Autodesk Fusion 360 part; units mm, degrees
(part 4 of 8)
sketch "SW5 spring 2 release 1 profile" plane through (0, -2.056, 23.4999) normal (0, -0.087156, 0.996195) x (1, 0, 0)
  line L0 (45.7157, 53.0972) -> (49.3, 53.0972)
  line L1 (49.3, 53.0972) -> (49.3, 53.6972)
  line L2 (49.3, 53.6972) -> (45.7157, 53.6972)
  line L3 (45.7157, 53.6972) -> (45.7157, 53.0972)
  dimension "d1355" = 45.7157
  dimension "d1356" = 53.0972
  dimension "d1357" = 3.5843
  dimension "d1358" = 0.6
  constraint horizontal L0
  constraint vertical L1
  constraint horizontal L2
  constraint vertical L3
  measures "d1355" horizontal distance of origin L0.start
  measures "d1356" vertical distance of origin L0.start
  measures "d1357" distance of L0.start L0.end
  measures "d1358" distance of L0.end L1.end
extrude "SW5 spring 2 release 1" cut sketch "SW5 spring 2 release 1 profile" against normal blind 10.7 bodies 2
sketch "SW5 spring 2 release 2 profile" plane through (0, -2.056, 23.4999) normal (0, -0.087156, 0.996195) x (1, 0, 0)
  line L0 (45.7157, 55.6972) -> (49.3, 55.6972)
  line L1 (49.3, 55.6972) -> (49.3, 56.2972)
  line L2 (49.3, 56.2972) -> (45.7157, 56.2972)
  line L3 (45.7157, 56.2972) -> (45.7157, 55.6972)
  dimension "d1361" = 45.7157
  dimension "d1362" = 55.6972
  dimension "d1363" = 3.5843
  dimension "d1364" = 0.6
  constraint horizontal L0
  constraint vertical L1
  constraint horizontal L2
  constraint vertical L3
  measures "d1361" horizontal distance of origin L0.start
  measures "d1362" vertical distance of origin L0.start
  measures "d1363" distance of L0.start L0.end
  measures "d1364" distance of L0.end L1.end
extrude "SW5 spring 2 release 2" cut sketch "SW5 spring 2 release 2 profile" against normal blind 10.7 bodies 2
sketch "SW5 spring 2 inner clearance profile" plane through (0, -1.6638, 19.017) normal (0, -0.087156, 0.996195) x (1, 0, 0)
  line L0 (45.7157, 53.6972) -> (48.4, 53.6972)
  line L1 (48.4, 53.6972) -> (48.4, 55.6972)
  line L2 (48.4, 55.6972) -> (45.7157, 55.6972)
  line L3 (45.7157, 55.6972) -> (45.7157, 53.6972)
  dimension "d1367" = 45.7157
  dimension "d1368" = 53.6972
  dimension "d1369" = 2.6843
  dimension "d1370" = 2
  constraint horizontal L0
  constraint vertical L1
  constraint horizontal L2
  constraint vertical L3
  measures "d1367" horizontal distance of origin L0.start
  measures "d1368" vertical distance of origin L0.start
  measures "d1369" distance of L0.start L0.end
  measures "d1370" distance of L0.end L1.end
extrude "SW5 spring 2 inner clearance" cut sketch "SW5 spring 2 inner clearance profile" against normal blind 6.2 bodies 2
sketch "SW5 spring 2 hook profile" plane through (0, -1.2106, 13.8368) normal (0, -0.087156, 0.996195) x (1, 0, 0)
  line L0 (45.2157, 53.6972) -> (49.2, 53.6972)
  line L1 (49.2, 53.6972) -> (49.2, 55.6972)
  line L2 (49.2, 55.6972) -> (45.2157, 55.6972)
  line L3 (45.2157, 55.6972) -> (45.2157, 53.6972)
  dimension "d1373" = 45.2157
  dimension "d1374" = 53.6972
  dimension "d1375" = 3.9843
  dimension "d1376" = 2
  constraint horizontal L0
  constraint vertical L1
  constraint horizontal L2
  constraint vertical L3
  measures "d1373" horizontal distance of origin L0.start
  measures "d1374" vertical distance of origin L0.start
  measures "d1375" distance of L0.start L0.end
  measures "d1376" distance of L0.end L1.end
extrude "SW5 spring 2 retaining hook" add sketch "SW5 spring 2 hook profile" against normal blind 0.8 bodies 2
chamfer "SW5 spring 2 45 degree lead-in" distance 0.35 angle 45 1 edges at (45.2157, 53.3482, 17.807) tangent chain off on bodies 2
sketch "SW5 support 1 reinforced stem profile" plane through (0, 0, 2) normal (0, 0, 1) x (1, 0, 0)
  line L0 (36.3, 45.9145) -> (38.7, 45.9145)
  line L1 (38.7, 45.9145) -> (38.7, 50.9145)
  line L2 (38.7, 50.9145) -> (36.3, 50.9145)
  line L3 (36.3, 50.9145) -> (36.3, 45.9145)
  dimension "d1380" = 36.3
  dimension "d1381" = 45.9145
  dimension "d1382" = 2.4
  dimension "d1383" = 5
  constraint horizontal L0
  constraint vertical L1
  constraint horizontal L2
  constraint vertical L3
  measures "d1380" horizontal distance of origin L0.start
  measures "d1381" vertical distance of origin L0.start
  measures "d1382" distance of L0.start L0.end
  measures "d1383" distance of L0.end L1.end
extrude "SW5 support 1 reinforced stem" add sketch "SW5 support 1 reinforced stem profile" along normal blind 13.9777 bodies 3
sketch "SW5 support 1 profile" plane through (0, 0, 2) normal (0, 0, 1) x (1, 0, 0)
  line L0 (37, 46.9145) -> (38, 46.9145)
  line L1 (38, 46.9145) -> (38, 49.9145)
  line L2 (38, 49.9145) -> (37, 49.9145)
  line L3 (37, 49.9145) -> (37, 46.9145)
  dimension "d1386" = 37
  dimension "d1387" = 46.9145
  dimension "d1388" = 1
  dimension "d1389" = 3
  constraint horizontal L0
  constraint vertical L1
  constraint horizontal L2
  constraint vertical L3
  measures "d1386" horizontal distance of origin L0.start
  measures "d1387" vertical distance of origin L0.start
  measures "d1388" distance of L0.start L0.end
  measures "d1389" distance of L0.end L1.end
extrude "SW5 support 1" add sketch "SW5 support 1 profile" along normal blind 16.4777 bodies 3
sketch "SW5 support 1 cap profile" plane through (0, -1.1931, 13.6376) normal (0, -0.087156, 0.996195) x (1, 0, 0)
  line L0 (36.9, 47.7972) -> (38.1, 47.7972)
  line L1 (38.1, 47.7972) -> (38.1, 51.7972)
  line L2 (38.1, 51.7972) -> (36.9, 51.7972)
  line L3 (36.9, 51.7972) -> (36.9, 47.7972)
  dimension "d1392" = 36.9
  dimension "d1393" = 47.7972
  dimension "d1394" = 1.2
  dimension "d1395" = 4
  constraint horizontal L0
  constraint vertical L1
  constraint horizontal L2
  constraint vertical L3
  measures "d1392" horizontal distance of origin L0.start
  measures "d1393" vertical distance of origin L0.start
  measures "d1394" distance of L0.start L0.end
  measures "d1395" distance of L0.end L1.end
extrude "SW5 support 1 inclined cap" cut sketch "SW5 support 1 cap profile" along normal blind 39.0612 bodies 3
sketch "SW5 support 2 reinforced stem profile" plane through (0, 0, 2) normal (0, 0, 1) x (1, 0, 0)
  line L0 (41.3, 45.9145) -> (43.7, 45.9145)
  line L1 (43.7, 45.9145) -> (43.7, 50.9145)
  line L2 (43.7, 50.9145) -> (41.3, 50.9145)
  line L3 (41.3, 50.9145) -> (41.3, 45.9145)
  dimension "d1398" = 41.3
  dimension "d1399" = 45.9145
  dimension "d1400" = 2.4
  dimension "d1401" = 5
  constraint horizontal L0
  constraint vertical L1
  constraint horizontal L2
  constraint vertical L3
  measures "d1398" horizontal distance of origin L0.start
  measures "d1399" vertical distance of origin L0.start
  measures "d1400" distance of L0.start L0.end
  measures "d1401" distance of L0.end L1.end
extrude "SW5 support 2 reinforced stem" add sketch "SW5 support 2 reinforced stem profile" along normal blind 13.9777 bodies 3
sketch "SW5 support 2 profile" plane through (0, 0, 2) normal (0, 0, 1) x (1, 0, 0)
  line L0 (42, 46.9145) -> (43, 46.9145)
  line L1 (43, 46.9145) -> (43, 49.9145)
  line L2 (43, 49.9145) -> (42, 49.9145)
  line L3 (42, 49.9145) -> (42, 46.9145)
  dimension "d1404" = 42
  dimension "d1405" = 46.9145
  dimension "d1406" = 1
  dimension "d1407" = 3
  constraint horizontal L0
  constraint vertical L1
  constraint horizontal L2
  constraint vertical L3
  measures "d1404" horizontal distance of origin L0.start
  measures "d1405" vertical distance of origin L0.start
  measures "d1406" distance of L0.start L0.end
  measures "d1407" distance of L0.end L1.end
extrude "SW5 support 2" add sketch "SW5 support 2 profile" along normal blind 16.4777 bodies 3
sketch "SW5 support 2 cap profile" plane through (0, -1.1931, 13.6376) normal (0, -0.087156, 0.996195) x (1, 0, 0)
  line L0 (41.9, 47.7972) -> (43.1, 47.7972)
  line L1 (43.1, 47.7972) -> (43.1, 51.7972)
  line L2 (43.1, 51.7972) -> (41.9, 51.7972)
  line L3 (41.9, 51.7972) -> (41.9, 47.7972)
  dimension "d1410" = 41.9
  dimension "d1411" = 47.7972
  dimension "d1412" = 1.2
  dimension "d1413" = 4
  constraint horizontal L0
  constraint vertical L1
  constraint horizontal L2
  constraint vertical L3
  measures "d1410" horizontal distance of origin L0.start
  measures "d1411" vertical distance of origin L0.start
  measures "d1412" distance of L0.start L0.end
  measures "d1413" distance of L0.end L1.end
extrude "SW5 support 2 inclined cap" cut sketch "SW5 support 2 cap profile" along normal blind 39.0612 bodies 3
sketch "SW6 receiver profile" plane through (0, -2.1431, 24.4961) normal (0, -0.087156, 0.996195) x (1, 0, 0)
  line L0 (55.3, 42.1972) -> (73.7, 42.1972)
  line L1 (73.7, 42.1972) -> (73.7, 59.7972)
  line L2 (73.7, 59.7972) -> (55.3, 59.7972)
  line L3 (55.3, 59.7972) -> (55.3, 42.1972)
  dimension "d1416" = 55.3
  dimension "d1417" = 42.1972
  dimension "d1418" = 18.4
  dimension "d1419" = 17.6
  constraint horizontal L0
  constraint vertical L1
  constraint horizontal L2
  constraint vertical L3
  measures "d1416" horizontal distance of origin L0.start
  measures "d1417" vertical distance of origin L0.start
  measures "d1418" distance of L0.start L0.end
  measures "d1419" distance of L0.end L1.end
extrude "SW6 integrated receiver" add sketch "SW6 receiver profile" against normal blind 11.5 bodies 2
sketch "SW6 switch lower clearance profile" plane through (0, -2.1431, 24.4961) normal (0, -0.087156, 0.996195) x (1, 0, 0)
  line L0 (56.5, 42.9972) -> (72.5, 42.9972)
  line L1 (72.5, 42.9972) -> (72.5, 58.9972)
  line L2 (72.5, 58.9972) -> (56.5, 58.9972)
  line L3 (56.5, 58.9972) -> (56.5, 42.9972)
  dimension "d1422" = 56.5
  dimension "d1423" = 42.9972
  dimension "d1424" = 16
  dimension "d1425" = 16
  constraint horizontal L0
  constraint vertical L1
  constraint horizontal L2
  constraint vertical L3
  measures "d1422" horizontal distance of origin L0.start
  measures "d1423" vertical distance of origin L0.start
  measures "d1424" distance of L0.start L0.end
  measures "d1425" distance of L0.end L1.end
extrude "SW6 switch lower clearance" cut sketch "SW6 switch lower clearance profile" against normal blind 5.5 bodies 2
sketch "SW6 holder pocket profile" plane through (0, -1.6638, 19.017) normal (0, -0.087156, 0.996195) x (1, 0, 0)
  line L0 (58.7843, 45.9226) -> (70.2157, 45.9226)
  line L1 (70.2157, 45.9226) -> (70.2157, 56.0717)
  line L2 (70.2157, 56.0717) -> (58.7843, 56.0717)
  line L3 (58.7843, 56.0717) -> (58.7843, 45.9226)
  dimension "d1428" = 58.7843
  dimension "d1429" = 45.9226
  dimension "d1430" = 11.4315
  dimension "d1431" = 10.1491
  constraint horizontal L0
  constraint vertical L1
  constraint horizontal L2
  constraint vertical L3
  measures "d1428" horizontal distance of origin L0.start
  measures "d1429" vertical distance of origin L0.start
  measures "d1430" distance of L0.start L0.end
  measures "d1431" distance of L0.end L1.end
extrude "SW6 open-bottom holder pocket" cut sketch "SW6 holder pocket profile" against normal blind 6.2 bodies 2
sketch "SW6 spring 1 release 1 profile" plane through (0, -2.056, 23.4999) normal (0, -0.087156, 0.996195) x (1, 0, 0)
  line L0 (55.2, 53.0972) -> (58.7843, 53.0972)
  line L1 (58.7843, 53.0972) -> (58.7843, 53.6972)
  line L2 (58.7843, 53.6972) -> (55.2, 53.6972)
  line L3 (55.2, 53.6972) -> (55.2, 53.0972)
  dimension "d1434" = 55.2
  dimension "d1435" = 53.0972
  dimension "d1436" = 3.5843
  dimension "d1437" = 0.6
  constraint horizontal L0
  constraint vertical L1
  constraint horizontal L2
  constraint vertical L3
  measures "d1434" horizontal distance of origin L0.start
  measures "d1435" vertical distance of origin L0.start
  measures "d1436" distance of L0.start L0.end
  measures "d1437" distance of L0.end L1.end
extrude "SW6 spring 1 release 1" cut sketch "SW6 spring 1 release 1 profile" against normal blind 10.7 bodies 2
sketch "SW6 spring 1 release 2 profile" plane through (0, -2.056, 23.4999) normal (0, -0.087156, 0.996195) x (1, 0, 0)
  line L0 (55.2, 55.6972) -> (58.7843, 55.6972)
  line L1 (58.7843, 55.6972) -> (58.7843, 56.2972)
  line L2 (58.7843, 56.2972) -> (55.2, 56.2972)
  line L3 (55.2, 56.2972) -> (55.2, 55.6972)
  dimension "d1440" = 55.2
  dimension "d1441" = 55.6972
  dimension "d1442" = 3.5843
  dimension "d1443" = 0.6
  constraint horizontal L0
  constraint vertical L1
  constraint horizontal L2
  constraint vertical L3
  measures "d1440" horizontal distance of origin L0.start
  measures "d1441" vertical distance of origin L0.start
  measures "d1442" distance of L0.start L0.end
  measures "d1443" distance of L0.end L1.end
extrude "SW6 spring 1 release 2" cut sketch "SW6 spring 1 release 2 profile" against normal blind 10.7 bodies 2
sketch "SW6 spring 1 inner clearance profile" plane through (0, -1.6638, 19.017) normal (0, -0.087156, 0.996195) x (1, 0, 0)
  line L0 (56.1, 53.6972) -> (58.7843, 53.6972)
  line L1 (58.7843, 53.6972) -> (58.7843, 55.6972)
  line L2 (58.7843, 55.6972) -> (56.1, 55.6972)
  line L3 (56.1, 55.6972) -> (56.1, 53.6972)
  dimension "d1446" = 56.1
  dimension "d1447" = 53.6972
  dimension "d1448" = 2.6843
  dimension "d1449" = 2
  constraint horizontal L0
  constraint vertical L1
  constraint horizontal L2
  constraint vertical L3
  measures "d1446" horizontal distance of origin L0.start
  measures "d1447" vertical distance of origin L0.start
  measures "d1448" distance of L0.start L0.end
  measures "d1449" distance of L0.end L1.end
extrude "SW6 spring 1 inner clearance" cut sketch "SW6 spring 1 inner clearance profile" against normal blind 6.2 bodies 2
sketch "SW6 spring 1 hook profile" plane through (0, -1.2106, 13.8368) normal (0, -0.087156, 0.996195) x (1, 0, 0)
  line L0 (55.3, 53.6972) -> (59.2843, 53.6972)
  line L1 (59.2843, 53.6972) -> (59.2843, 55.6972)
  line L2 (59.2843, 55.6972) -> (55.3, 55.6972)
  line L3 (55.3, 55.6972) -> (55.3, 53.6972)
  dimension "d1452" = 55.3
  dimension "d1453" = 53.6972
  dimension "d1454" = 3.9843
  dimension "d1455" = 2
  constraint horizontal L0
  constraint vertical L1
  constraint horizontal L2
  constraint vertical L3
  measures "d1452" horizontal distance of origin L0.start
  measures "d1453" vertical distance of origin L0.start
  measures "d1454" distance of L0.start L0.end
  measures "d1455" distance of L0.end L1.end
extrude "SW6 spring 1 retaining hook" add sketch "SW6 spring 1 hook profile" against normal blind 0.8 bodies 2
chamfer "SW6 spring 1 45 degree lead-in" distance 0.35 angle 45 1 edges at (59.2843, 53.3482, 17.807) tangent chain off on bodies 2
sketch "SW6 spring 2 release 1 profile" plane through (0, -2.056, 23.4999) normal (0, -0.087156, 0.996195) x (1, 0, 0)
  line L0 (70.2157, 53.0972) -> (73.8, 53.0972)
  line L1 (73.8, 53.0972) -> (73.8, 53.6972)
  line L2 (73.8, 53.6972) -> (70.2157, 53.6972)
  line L3 (70.2157, 53.6972) -> (70.2157, 53.0972)
  dimension "d1459" = 70.2157
  dimension "d1460" = 53.0972
  dimension "d1461" = 3.5843
  dimension "d1462" = 0.6
  constraint horizontal L0
  constraint vertical L1
  constraint horizontal L2
  constraint vertical L3
  measures "d1459" horizontal distance of origin L0.start
  measures "d1460" vertical distance of origin L0.start
  measures "d1461" distance of L0.start L0.end
  measures "d1462" distance of L0.end L1.end
extrude "SW6 spring 2 release 1" cut sketch "SW6 spring 2 release 1 profile" against normal blind 10.7 bodies 2
sketch "SW6 spring 2 release 2 profile" plane through (0, -2.056, 23.4999) normal (0, -0.087156, 0.996195) x (1, 0, 0)
  line L0 (70.2157, 55.6972) -> (73.8, 55.6972)
  line L1 (73.8, 55.6972) -> (73.8, 56.2972)
  line L2 (73.8, 56.2972) -> (70.2157, 56.2972)
  line L3 (70.2157, 56.2972) -> (70.2157, 55.6972)
  dimension "d1465" = 70.2157
  dimension "d1466" = 55.6972
  dimension "d1467" = 3.5843
  dimension "d1468" = 0.6
  constraint horizontal L0
  constraint vertical L1
  constraint horizontal L2
  constraint vertical L3
  measures "d1465" horizontal distance of origin L0.start
  measures "d1466" vertical distance of origin L0.start
  measures "d1467" distance of L0.start L0.end
  measures "d1468" distance of L0.end L1.end
extrude "SW6 spring 2 release 2" cut sketch "SW6 spring 2 release 2 profile" against normal blind 10.7 bodies 2
sketch "SW6 spring 2 inner clearance profile" plane through (0, -1.6638, 19.017) normal (0, -0.087156, 0.996195) x (1, 0, 0)
  line L0 (70.2157, 53.6972) -> (72.9, 53.6972)
  line L1 (72.9, 53.6972) -> (72.9, 55.6972)
  line L2 (72.9, 55.6972) -> (70.2157, 55.6972)
  line L3 (70.2157, 55.6972) -> (70.2157, 53.6972)
  dimension "d1471" = 70.2157
  dimension "d1472" = 53.6972
  dimension "d1473" = 2.6843
  dimension "d1474" = 2
  constraint horizontal L0
  constraint vertical L1
  constraint horizontal L2
  constraint vertical L3
  measures "d1471" horizontal distance of origin L0.start
  measures "d1472" vertical distance of origin L0.start
  measures "d1473" distance of L0.start L0.end
  measures "d1474" distance of L0.end L1.end
extrude "SW6 spring 2 inner clearance" cut sketch "SW6 spring 2 inner clearance profile" against normal blind 6.2 bodies 2
sketch "SW6 spring 2 hook profile" plane through (0, -1.2106, 13.8368) normal (0, -0.087156, 0.996195) x (1, 0, 0)
  line L0 (69.7157, 53.6972) -> (73.7, 53.6972)
  line L1 (73.7, 53.6972) -> (73.7, 55.6972)
  line L2 (73.7, 55.6972) -> (69.7157, 55.6972)
  line L3 (69.7157, 55.6972) -> (69.7157, 53.6972)
  dimension "d1477" = 69.7157
  dimension "d1478" = 53.6972
  dimension "d1479" = 3.9843
  dimension "d1480" = 2
  constraint horizontal L0
  constraint vertical L1
  constraint horizontal L2
  constraint vertical L3
  measures "d1477" horizontal distance of origin L0.start
  measures "d1478" vertical distance of origin L0.start
  measures "d1479" distance of L0.start L0.end
  measures "d1480" distance of L0.end L1.end
extrude "SW6 spring 2 retaining hook" add sketch "SW6 spring 2 hook profile" against normal blind 0.8 bodies 2
chamfer "SW6 spring 2 45 degree lead-in" distance 0.35 angle 45 1 edges at (69.7157, 53.3482, 17.807) tangent chain off on bodies 2
sketch "SW6 support 1 reinforced stem profile" plane through (0, 0, 2) normal (0, 0, 1) x (1, 0, 0)
  line L0 (60.8, 45.9145) -> (63.2, 45.9145)
  line L1 (63.2, 45.9145) -> (63.2, 50.9145)
  line L2 (63.2, 50.9145) -> (60.8, 50.9145)
  line L3 (60.8, 50.9145) -> (60.8, 45.9145)
  dimension "d1484" = 60.8
  dimension "d1485" = 45.9145
  dimension "d1486" = 2.4
  dimension "d1487" = 5
  constraint horizontal L0
  constraint vertical L1
  constraint horizontal L2
  constraint vertical L3
  measures "d1484" horizontal distance of origin L0.start
  measures "d1485" vertical distance of origin L0.start
  measures "d1486" distance of L0.start L0.end
  measures "d1487" distance of L0.end L1.end
extrude "SW6 support 1 reinforced stem" add sketch "SW6 support 1 reinforced stem profile" along normal blind 13.9777 bodies 3
sketch "SW6 support 1 profile" plane through (0, 0, 2) normal (0, 0, 1) x (1, 0, 0)
  line L0 (61.5, 46.9145) -> (62.5, 46.9145)
  line L1 (62.5, 46.9145) -> (62.5, 49.9145)
  line L2 (62.5, 49.9145) -> (61.5, 49.9145)
  line L3 (61.5, 49.9145) -> (61.5, 46.9145)
  dimension "d1490" = 61.5
  dimension "d1491" = 46.9145
  dimension "d1492" = 1
  dimension "d1493" = 3
  constraint horizontal L0
  constraint vertical L1
  constraint horizontal L2
  constraint vertical L3
  measures "d1490" horizontal distance of origin L0.start
  measures "d1491" vertical distance of origin L0.start
  measures "d1492" distance of L0.start L0.end
  measures "d1493" distance of L0.end L1.end
extrude "SW6 support 1" add sketch "SW6 support 1 profile" along normal blind 16.4777 bodies 3
sketch "SW6 support 1 cap profile" plane through (0, -1.1931, 13.6376) normal (0, -0.087156, 0.996195) x (1, 0, 0)
  line L0 (61.4, 47.7972) -> (62.6, 47.7972)
  line L1 (62.6, 47.7972) -> (62.6, 51.7972)
  line L2 (62.6, 51.7972) -> (61.4, 51.7972)
  line L3 (61.4, 51.7972) -> (61.4, 47.7972)
  dimension "d1496" = 61.4
  dimension "d1497" = 47.7972
  dimension "d1498" = 1.2
  dimension "d1499" = 4
  constraint horizontal L0
  constraint vertical L1
  constraint horizontal L2
  constraint vertical L3
  measures "d1496" horizontal distance of origin L0.start
  measures "d1497" vertical distance of origin L0.start
  measures "d1498" distance of L0.start L0.end
  measures "d1499" distance of L0.end L1.end
extrude "SW6 support 1 inclined cap" cut sketch "SW6 support 1 cap profile" along normal blind 39.0612 bodies 3
sketch "SW6 support 2 reinforced stem profile" plane through (0, 0, 2) normal (0, 0, 1) x (1, 0, 0)
  line L0 (65.8, 45.9145) -> (68.2, 45.9145)
  line L1 (68.2, 45.9145) -> (68.2, 50.9145)
  line L2 (68.2, 50.9145) -> (65.8, 50.9145)
  line L3 (65.8, 50.9145) -> (65.8, 45.9145)
  dimension "d1502" = 65.8
  dimension "d1503" = 45.9145
  dimension "d1504" = 2.4
  dimension "d1505" = 5
  constraint horizontal L0
  constraint vertical L1
  constraint horizontal L2
  constraint vertical L3
  measures "d1502" horizontal distance of origin L0.start
  measures "d1503" vertical distance of origin L0.start
  measures "d1504" distance of L0.start L0.end
  measures "d1505" distance of L0.end L1.end
extrude "SW6 support 2 reinforced stem" add sketch "SW6 support 2 reinforced stem profile" along normal blind 13.9777 bodies 3
sketch "SW6 support 2 profile" plane through (0, 0, 2) normal (0, 0, 1) x (1, 0, 0)
  line L0 (66.5, 46.9145) -> (67.5, 46.9145)
  line L1 (67.5, 46.9145) -> (67.5, 49.9145)
  line L2 (67.5, 49.9145) -> (66.5, 49.9145)
  line L3 (66.5, 49.9145) -> (66.5, 46.9145)
  dimension "d1508" = 66.5
  dimension "d1509" = 46.9145
  dimension "d1510" = 1
  dimension "d1511" = 3
  constraint horizontal L0
  constraint vertical L1
  constraint horizontal L2
  constraint vertical L3
  measures "d1508" horizontal distance of origin L0.start
  measures "d1509" vertical distance of origin L0.start
  measures "d1510" distance of L0.start L0.end
  measures "d1511" distance of L0.end L1.end
extrude "SW6 support 2" add sketch "SW6 support 2 profile" along normal blind 16.4777 bodies 3
sketch "SW6 support 2 cap profile" plane through (0, -1.1931, 13.6376) normal (0, -0.087156, 0.996195) x (1, 0, 0)
  line L0 (66.4, 47.7972) -> (67.6, 47.7972)
  line L1 (67.6, 47.7972) -> (67.6, 51.7972)
  line L2 (67.6, 51.7972) -> (66.4, 51.7972)
  line L3 (66.4, 51.7972) -> (66.4, 47.7972)
  dimension "d1514" = 66.4
  dimension "d1515" = 47.7972
  dimension "d1516" = 1.2
  dimension "d1517" = 4
  constraint horizontal L0
  constraint vertical L1
  constraint horizontal L2
  constraint vertical L3
  measures "d1514" horizontal distance of origin L0.start
  measures "d1515" vertical distance of origin L0.start
  measures "d1516" distance of L0.start L0.end
  measures "d1517" distance of L0.end L1.end
extrude "SW6 support 2 inclined cap" cut sketch "SW6 support 2 cap profile" along normal blind 39.0612 bodies 3
sketch "OLED clearance after switch receivers profile" plane through (0, -2.2739, 25.9904) normal (0, -0.087156, 0.996195) x (1, 0, 0)
  line L0 (5.55, 59.2972) -> (41.95, 59.2972)
  line L1 (41.95, 59.2972) -> (41.95, 93.6972)
  line L2 (41.95, 93.6972) -> (5.55, 93.6972)
  line L3 (5.55, 93.6972) -> (5.55, 59.2972)
  dimension "d1520" = 5.55
  dimension "d1521" = 59.2972
  dimension "d1522" = 36.4
  dimension "d1523" = 34.4
  constraint horizontal L0
  constraint vertical L1
  constraint horizontal L2
  constraint vertical L3
  measures "d1520" horizontal distance of origin L0.start
  measures "d1521" vertical distance of origin L0.start
  measures "d1522" distance of L0.start L0.end
  measures "d1523" distance of L0.end L1.end
extrude "OLED clearance after switch receivers" cut sketch "OLED clearance after switch receivers profile" against normal blind 1.8 bodies 2
sketch "Switch trial plate profile" plane through (0, -2.2739, 25.9904) normal (0, -0.087156, 0.996195) x (1, 0, 0)
  line L0 (104, 15.4972) -> (126, 15.4972)
  line L1 (126, 15.4972) -> (126, 37.4972)
  line L2 (126, 37.4972) -> (104, 37.4972)
  line L3 (104, 37.4972) -> (104, 15.4972)
  dimension "d1526" = 104
  dimension "d1527" = 15.4972
  dimension "d1528" = 22
  dimension "d1529" = 22
  constraint horizontal L0
  constraint vertical L1
  constraint horizontal L2
  constraint vertical L3
  measures "d1526" horizontal distance of origin L0.start
  measures "d1527" vertical distance of origin L0.start
  measures "d1528" distance of L0.start L0.end
  measures "d1529" distance of L0.end L1.end
extrude "Switch trial plate" add sketch "Switch trial plate profile" against normal blind 1.5 separate body makes body 5
sketch "Switch trial clip seat profile" plane through (0, -2.2739, 25.9904) normal (0, -0.087156, 0.996195) x (1, 0, 0)
  line L0 (107.95, 19.4472) -> (122.05, 19.4472)
  line L1 (122.05, 19.4472) -> (122.05, 33.5472)
  line L2 (122.05, 33.5472) -> (107.95, 33.5472)
  line L3 (107.95, 33.5472) -> (107.95, 19.4472)
  dimension "d1532" = 107.95
  dimension "d1533" = 19.4472
  dimension "d1534" = 14.1
  dimension "d1535" = 14.1
  constraint horizontal L0
  constraint vertical L1
  constraint horizontal L2
  constraint vertical L3
  measures "d1532" horizontal distance of origin L0.start
  measures "d1533" vertical distance of origin L0.start
  measures "d1534" distance of L0.start L0.end
  measures "d1535" distance of L0.end L1.end
extrude "Switch trial clip seat" cut sketch "Switch trial clip seat profile" against normal blind 1.6 bodies 5
sketch "Switch trial receiver profile" plane through (0, -2.1431, 24.4961) normal (0, -0.087156, 0.996195) x (1, 0, 0)
  line L0 (105.8, 17.6972) -> (124.2, 17.6972)
  line L1 (124.2, 17.6972) -> (124.2, 35.2972)
  line L2 (124.2, 35.2972) -> (105.8, 35.2972)
  line L3 (105.8, 35.2972) -> (105.8, 17.6972)
  dimension "d1538" = 105.8
  dimension "d1539" = 17.6972
  dimension "d1540" = 18.4
  dimension "d1541" = 17.6
  constraint horizontal L0
  constraint vertical L1
  constraint horizontal L2
  constraint vertical L3
  measures "d1538" horizontal distance of origin L0.start
  measures "d1539" vertical distance of origin L0.start
  measures "d1540" distance of L0.start L0.end
  measures "d1541" distance of L0.end L1.end
extrude "Switch trial integrated receiver" add sketch "Switch trial receiver profile" against normal blind 11.5 bodies 5
sketch "Switch trial switch lower clearance profile" plane through (0, -2.1431, 24.4961) normal (0, -0.087156, 0.996195) x (1, 0, 0)
  line L0 (107, 18.4972) -> (123, 18.4972)
  line L1 (123, 18.4972) -> (123, 34.4972)
  line L2 (123, 34.4972) -> (107, 34.4972)
  line L3 (107, 34.4972) -> (107, 18.4972)
  dimension "d1544" = 107
  dimension "d1545" = 18.4972
  dimension "d1546" = 16
  dimension "d1547" = 16
  constraint horizontal L0
  constraint vertical L1
  constraint horizontal L2
  constraint vertical L3
  measures "d1544" horizontal distance of origin L0.start
  measures "d1545" vertical distance of origin L0.start
  measures "d1546" distance of L0.start L0.end
  measures "d1547" distance of L0.end L1.end
extrude "Switch trial switch lower clearance" cut sketch "Switch trial switch lower clearance profile" against normal blind 5.5 bodies 5
sketch "Switch trial holder pocket profile" plane through (0, -1.6638, 19.017) normal (0, -0.087156, 0.996195) x (1, 0, 0)
  line L0 (109.2843, 21.4226) -> (120.7157, 21.4226)
  line L1 (120.7157, 21.4226) -> (120.7157, 31.5717)
  line L2 (120.7157, 31.5717) -> (109.2843, 31.5717)
  line L3 (109.2843, 31.5717) -> (109.2843, 21.4226)
  dimension "d1550" = 109.2843
  dimension "d1551" = 21.4226
  dimension "d1552" = 11.4315
  dimension "d1553" = 10.1491
  constraint horizontal L0
  constraint vertical L1
  constraint horizontal L2
  constraint vertical L3
  measures "d1550" horizontal distance of origin L0.start
  measures "d1551" vertical distance of origin L0.start
  measures "d1552" distance of L0.start L0.end
  measures "d1553" distance of L0.end L1.end
extrude "Switch trial open-bottom holder pocket" cut sketch "Switch trial holder pocket profile" against normal blind 6.2 bodies 5
sketch "Switch trial spring 1 release 1 profile" plane through (0, -2.056, 23.4999) normal (0, -0.087156, 0.996195) x (1, 0, 0)
  line L0 (105.7, 28.5972) -> (109.2843, 28.5972)
  line L1 (109.2843, 28.5972) -> (109.2843, 29.1972)
  line L2 (109.2843, 29.1972) -> (105.7, 29.1972)
  line L3 (105.7, 29.1972) -> (105.7, 28.5972)
  dimension "d1556" = 105.7
  dimension "d1557" = 28.5972
  dimension "d1558" = 3.5843
  dimension "d1559" = 0.6
  constraint horizontal L0
  constraint vertical L1
  constraint horizontal L2
  constraint vertical L3
  measures "d1556" horizontal distance of origin L0.start
  measures "d1557" vertical distance of origin L0.start
  measures "d1558" distance of L0.start L0.end
  measures "d1559" distance of L0.end L1.end
extrude "Switch trial spring 1 release 1" cut sketch "Switch trial spring 1 release 1 profile" against normal blind 10.7 bodies 5
sketch "Switch trial spring 1 release 2 profile" plane through (0, -2.056, 23.4999) normal (0, -0.087156, 0.996195) x (1, 0, 0)
  line L0 (105.7, 31.1972) -> (109.2843, 31.1972)
  line L1 (109.2843, 31.1972) -> (109.2843, 31.7972)
  line L2 (109.2843, 31.7972) -> (105.7, 31.7972)
  line L3 (105.7, 31.7972) -> (105.7, 31.1972)
  dimension "d1562" = 105.7
  dimension "d1563" = 31.1972
  dimension "d1564" = 3.5843
  dimension "d1565" = 0.6
  constraint horizontal L0
  constraint vertical L1
  constraint horizontal L2
  constraint vertical L3
  measures "d1562" horizontal distance of origin L0.start
  measures "d1563" vertical distance of origin L0.start
  measures "d1564" distance of L0.start L0.end
  measures "d1565" distance of L0.end L1.end
extrude "Switch trial spring 1 release 2" cut sketch "Switch trial spring 1 release 2 profile" against normal blind 10.7 bodies 5
sketch "Switch trial spring 1 inner clearance profile" plane through (0, -1.6638, 19.017) normal (0, -0.087156, 0.996195) x (1, 0, 0)
  line L0 (106.6, 29.1972) -> (109.2843, 29.1972)
  line L1 (109.2843, 29.1972) -> (109.2843, 31.1972)
  line L2 (109.2843, 31.1972) -> (106.6, 31.1972)
  line L3 (106.6, 31.1972) -> (106.6, 29.1972)
  dimension "d1568" = 106.6
  dimension "d1569" = 29.1972
  dimension "d1570" = 2.6843
  dimension "d1571" = 2
  constraint horizontal L0
  constraint vertical L1
  constraint horizontal L2
  constraint vertical L3
  measures "d1568" horizontal distance of origin L0.start
  measures "d1569" vertical distance of origin L0.start
  measures "d1570" distance of L0.start L0.end
  measures "d1571" distance of L0.end L1.end
extrude "Switch trial spring 1 inner clearance" cut sketch "Switch trial spring 1 inner clearance profile" against normal blind 6.2 bodies 5
sketch "Switch trial spring 1 hook profile" plane through (0, -1.2106, 13.8368) normal (0, -0.087156, 0.996195) x (1, 0, 0)
  line L0 (105.8, 29.1972) -> (109.7843, 29.1972)
  line L1 (109.7843, 29.1972) -> (109.7843, 31.1972)
  line L2 (109.7843, 31.1972) -> (105.8, 31.1972)
  line L3 (105.8, 31.1972) -> (105.8, 29.1972)
  dimension "d1574" = 105.8
  dimension "d1575" = 29.1972
  dimension "d1576" = 3.9843
  dimension "d1577" = 2
  constraint horizontal L0
  constraint vertical L1
  constraint horizontal L2
  constraint vertical L3
  measures "d1574" horizontal distance of origin L0.start
  measures "d1575" vertical distance of origin L0.start
  measures "d1576" distance of L0.start L0.end
  measures "d1577" distance of L0.end L1.end
extrude "Switch trial spring 1 retaining hook" add sketch "Switch trial spring 1 hook profile" against normal blind 0.8 bodies 5
chamfer "Switch trial spring 1 45 degree lead-in" distance 0.35 angle 45 1 edges at (109.7843, 28.9414, 15.6717) tangent chain off on bodies 5
sketch "Switch trial spring 2 release 1 profile" plane through (0, -2.056, 23.4999) normal (0, -0.087156, 0.996195) x (1, 0, 0)
  line L0 (120.7157, 28.5972) -> (124.3, 28.5972)
  line L1 (124.3, 28.5972) -> (124.3, 29.1972)
  line L2 (124.3, 29.1972) -> (120.7157, 29.1972)
  line L3 (120.7157, 29.1972) -> (120.7157, 28.5972)
  dimension "d1581" = 120.7157
  dimension "d1582" = 28.5972
  dimension "d1583" = 3.5843
  dimension "d1584" = 0.6
  constraint horizontal L0
  constraint vertical L1
  constraint horizontal L2
  constraint vertical L3
  measures "d1581" horizontal distance of origin L0.start
  measures "d1582" vertical distance of origin L0.start
  measures "d1583" distance of L0.start L0.end
  measures "d1584" distance of L0.end L1.end
extrude "Switch trial spring 2 release 1" cut sketch "Switch trial spring 2 release 1 profile" against normal blind 10.7 bodies 5
sketch "Switch trial spring 2 release 2 profile" plane through (0, -2.056, 23.4999) normal (0, -0.087156, 0.996195) x (1, 0, 0)
  line L0 (120.7157, 31.1972) -> (124.3, 31.1972)
  line L1 (124.3, 31.1972) -> (124.3, 31.7972)
  line L2 (124.3, 31.7972) -> (120.7157, 31.7972)
  line L3 (120.7157, 31.7972) -> (120.7157, 31.1972)
  dimension "d1587" = 120.7157
  dimension "d1588" = 31.1972
  dimension "d1589" = 3.5843
  dimension "d1590" = 0.6
  constraint horizontal L0
  constraint vertical L1
  constraint horizontal L2
  constraint vertical L3
  measures "d1587" horizontal distance of origin L0.start
  measures "d1588" vertical distance of origin L0.start
  measures "d1589" distance of L0.start L0.end
  measures "d1590" distance of L0.end L1.end
extrude "Switch trial spring 2 release 2" cut sketch "Switch trial spring 2 release 2 profile" against normal blind 10.7 bodies 5
sketch "Switch trial spring 2 inner clearance profile" plane through (0, -1.6638, 19.017) normal (0, -0.087156, 0.996195) x (1, 0, 0)
  line L0 (120.7157, 29.1972) -> (123.4, 29.1972)
  line L1 (123.4, 29.1972) -> (123.4, 31.1972)
  line L2 (123.4, 31.1972) -> (120.7157, 31.1972)
  line L3 (120.7157, 31.1972) -> (120.7157, 29.1972)
  dimension "d1593" = 120.7157
  dimension "d1594" = 29.1972
  dimension "d1595" = 2.6843
  dimension "d1596" = 2
  constraint horizontal L0
  constraint vertical L1
  constraint horizontal L2
  constraint vertical L3
  measures "d1593" horizontal distance of origin L0.start
  measures "d1594" vertical distance of origin L0.start
  measures "d1595" distance of L0.start L0.end
  measures "d1596" distance of L0.end L1.end
extrude "Switch trial spring 2 inner clearance" cut sketch "Switch trial spring 2 inner clearance profile" against normal blind 6.2 bodies 5
sketch "Switch trial spring 2 hook profile" plane through (0, -1.2106, 13.8368) normal (0, -0.087156, 0.996195) x (1, 0, 0)
  line L0 (120.2157, 29.1972) -> (124.2, 29.1972)
  line L1 (124.2, 29.1972) -> (124.2, 31.1972)
  line L2 (124.2, 31.1972) -> (120.2157, 31.1972)
  line L3 (120.2157, 31.1972) -> (120.2157, 29.1972)
  dimension "d1599" = 120.2157
  dimension "d1600" = 29.1972
  dimension "d1601" = 3.9843
  dimension "d1602" = 2
  constraint horizontal L0
  constraint vertical L1
  constraint horizontal L2
  constraint vertical L3
  measures "d1599" horizontal distance of origin L0.start
  measures "d1600" vertical distance of origin L0.start
  measures "d1601" distance of L0.start L0.end
  measures "d1602" distance of L0.end L1.end
extrude "Switch trial spring 2 retaining hook" add sketch "Switch trial spring 2 hook profile" against normal blind 0.8 bodies 5
chamfer "Switch trial spring 2 45 degree lead-in" distance 0.35 angle 45 1 edges at (120.2157, 28.9414, 15.6717) tangent chain off on bodies 5
sketch "Lid trial plate profile" plane through (0, 0, 0) normal (0, 0, 1) x (1, 0, 0)
  line L0 (104, 14.2032) -> (126, 14.2032)
  line L1 (126, 14.2032) -> (126, 36.2032)
  line L2 (126, 36.2032) -> (104, 36.2032)
  line L3 (104, 36.2032) -> (104, 14.2032)
  dimension "d1606" = 104
  dimension "d1607" = 14.2032
  dimension "d1608" = 22
  dimension "d1609" = 22
  constraint horizontal L0
  constraint vertical L1
  constraint horizontal L2
  constraint vertical L3
  measures "d1606" horizontal distance of origin L0.start
  measures "d1607" vertical distance of origin L0.start
  measures "d1608" distance of L0.start L0.end
  measures "d1609" distance of L0.end L1.end
extrude "Lid trial plate" add sketch "Lid trial plate profile" along normal blind 2 separate body makes body 6
sketch "Lid trial support 1 reinforced stem profile" plane through (0, 0, 2) normal (0, 0, 1) x (1, 0, 0)
  line L0 (111.3, 21.5078) -> (113.7, 21.5078)
  line L1 (113.7, 21.5078) -> (113.7, 26.5078)
  line L2 (113.7, 26.5078) -> (111.3, 26.5078)
  line L3 (111.3, 26.5078) -> (111.3, 21.5078)
  dimension "d1612" = 111.3
  dimension "d1613" = 21.5078
  dimension "d1614" = 2.4
  dimension "d1615" = 5
  constraint horizontal L0
  constraint vertical L1
  constraint horizontal L2
  constraint vertical L3
  measures "d1612" horizontal distance of origin L0.start
  measures "d1613" vertical distance of origin L0.start
  measures "d1614" distance of L0.start L0.end
  measures "d1615" distance of L0.end L1.end
extrude "Lid trial support 1 reinforced stem" add sketch "Lid trial support 1 reinforced stem profile" along normal blind 11.8423 bodies 6
sketch "Lid trial support 1 profile" plane through (0, 0, 2) normal (0, 0, 1) x (1, 0, 0)
  line L0 (112, 22.5078) -> (113, 22.5078)
  line L1 (113, 22.5078) -> (113, 25.5078)
  line L2 (113, 25.5078) -> (112, 25.5078)
  line L3 (112, 25.5078) -> (112, 22.5078)
  dimension "d1618" = 112
  dimension "d1619" = 22.5078
  dimension "d1620" = 1
  dimension "d1621" = 3
  constraint horizontal L0
  constraint vertical L1
  constraint horizontal L2
  constraint vertical L3
  measures "d1618" horizontal distance of origin L0.start
  measures "d1619" vertical distance of origin L0.start
  measures "d1620" distance of L0.start L0.end
  measures "d1621" distance of L0.end L1.end
extrude "Lid trial support 1" add sketch "Lid trial support 1 profile" along normal blind 14.3423 bodies 6
sketch "Lid trial support 1 cap profile" plane through (0, -1.1931, 13.6376) normal (0, -0.087156, 0.996195) x (1, 0, 0)
  line L0 (111.9, 23.2972) -> (113.1, 23.2972)
  line L1 (113.1, 23.2972) -> (113.1, 27.2972)
  line L2 (113.1, 27.2972) -> (111.9, 27.2972)
  line L3 (111.9, 27.2972) -> (111.9, 23.2972)
  dimension "d1624" = 111.9
  dimension "d1625" = 23.2972
  dimension "d1626" = 1.2
  dimension "d1627" = 4
  constraint horizontal L0
  constraint vertical L1
  constraint horizontal L2
  constraint vertical L3
  measures "d1624" horizontal distance of origin L0.start
  measures "d1625" vertical distance of origin L0.start
  measures "d1626" distance of L0.start L0.end
  measures "d1627" distance of L0.end L1.end
extrude "Lid trial support 1 inclined cap" cut sketch "Lid trial support 1 cap profile" along normal blind 39.0612 bodies 6
sketch "Lid trial support 2 reinforced stem profile" plane through (0, 0, 2) normal (0, 0, 1) x (1, 0, 0)
  line L0 (116.3, 21.5078) -> (118.7, 21.5078)
  line L1 (118.7, 21.5078) -> (118.7, 26.5078)
  line L2 (118.7, 26.5078) -> (116.3, 26.5078)
  line L3 (116.3, 26.5078) -> (116.3, 21.5078)
  dimension "d1630" = 116.3
  dimension "d1631" = 21.5078
  dimension "d1632" = 2.4
  dimension "d1633" = 5
  constraint horizontal L0
  constraint vertical L1
  constraint horizontal L2
  constraint vertical L3
  measures "d1630" horizontal distance of origin L0.start
  measures "d1631" vertical distance of origin L0.start
  measures "d1632" distance of L0.start L0.end
  measures "d1633" distance of L0.end L1.end
extrude "Lid trial support 2 reinforced stem" add sketch "Lid trial support 2 reinforced stem profile" along normal blind 11.8423 bodies 6
sketch "Lid trial support 2 profile" plane through (0, 0, 2) normal (0, 0, 1) x (1, 0, 0)
  line L0 (117, 22.5078) -> (118, 22.5078)
  line L1 (118, 22.5078) -> (118, 25.5078)
  line L2 (118, 25.5078) -> (117, 25.5078)
  line L3 (117, 25.5078) -> (117, 22.5078)
  dimension "d1636" = 117
  dimension "d1637" = 22.5078
  dimension "d1638" = 1
  dimension "d1639" = 3
  constraint horizontal L0
  constraint vertical L1
  constraint horizontal L2
  constraint vertical L3
  measures "d1636" horizontal distance of origin L0.start
  measures "d1637" vertical distance of origin L0.start
  measures "d1638" distance of L0.start L0.end
  measures "d1639" distance of L0.end L1.end
extrude "Lid trial support 2" add sketch "Lid trial support 2 profile" along normal blind 14.3423 bodies 6
sketch "Lid trial support 2 cap profile" plane through (0, -1.1931, 13.6376) normal (0, -0.087156, 0.996195) x (1, 0, 0)
  line L0 (116.9, 23.2972) -> (118.1, 23.2972)
  line L1 (118.1, 23.2972) -> (118.1, 27.2972)
  line L2 (118.1, 27.2972) -> (116.9, 27.2972)
  line L3 (116.9, 27.2972) -> (116.9, 23.2972)
  dimension "d1642" = 116.9
  dimension "d1643" = 23.2972
  dimension "d1644" = 1.2
  dimension "d1645" = 4
  constraint horizontal L0
  constraint vertical L1
  constraint horizontal L2
  constraint vertical L3
  measures "d1642" horizontal distance of origin L0.start
  measures "d1643" vertical distance of origin L0.start
  measures "d1644" distance of L0.start L0.end
  measures "d1645" distance of L0.end L1.end
extrude "Lid trial support 2 inclined cap" cut sketch "Lid trial support 2 cap profile" along normal blind 39.0612 bodies 6
sketch "SW1 upper stop 1 profile" plane through (0, -1.6638, 19.017) normal (0, -0.087156, 0.996195) x (1, 0, 0)
  line L0 (12, 30.4972) -> (13, 30.4972)
  line L1 (13, 30.4972) -> (13, 35.2972)
  line L2 (13, 35.2972) -> (12, 35.2972)
  line L3 (12, 35.2972) -> (12, 30.4972)
  dimension "d1648" = 12
  dimension "d1649" = 30.4972
  dimension "d1650" = 1
  dimension "d1651" = 4.8
  constraint horizontal L0
  constraint vertical L1
  constraint horizontal L2
  constraint vertical L3
  measures "d1648" horizontal distance of origin L0.start
  measures "d1649" vertical distance of origin L0.start
  measures "d1650" distance of L0.start L0.end
  measures "d1651" distance of L0.end L1.end
extrude "SW1 upper stop 1" add sketch "SW1 upper stop 1 profile" along normal blind 0.8 bodies 2
sketch "SW1 upper stop 2 profile" plane through (0, -1.6638, 19.017) normal (0, -0.087156, 0.996195) x (1, 0, 0)
  line L0 (18, 30.4972) -> (19, 30.4972)
  line L1 (19, 30.4972) -> (19, 35.2972)
  line L2 (19, 35.2972) -> (18, 35.2972)
  line L3 (18, 35.2972) -> (18, 30.4972)
  dimension "d1654" = 18
  dimension "d1655" = 30.4972
  dimension "d1656" = 1
  dimension "d1657" = 4.8
  constraint horizontal L0
  constraint vertical L1
  constraint horizontal L2
  constraint vertical L3
  measures "d1654" horizontal distance of origin L0.start
  measures "d1655" vertical distance of origin L0.start
  measures "d1656" distance of L0.start L0.end
  measures "d1657" distance of L0.end L1.end
extrude "SW1 upper stop 2" add sketch "SW1 upper stop 2 profile" along normal blind 0.8 bodies 2
sketch "SW2 upper stop 1 profile" plane through (0, -1.6638, 19.017) normal (0, -0.087156, 0.996195) x (1, 0, 0)
  line L0 (36.5, 30.4972) -> (37.5, 30.4972)
  line L1 (37.5, 30.4972) -> (37.5, 35.2972)
  line L2 (37.5, 35.2972) -> (36.5, 35.2972)
  line L3 (36.5, 35.2972) -> (36.5, 30.4972)
  dimension "d1660" = 36.5
  dimension "d1661" = 30.4972
  dimension "d1662" = 1
  dimension "d1663" = 4.8
  constraint horizontal L0
  constraint vertical L1
  constraint horizontal L2
  constraint vertical L3
  measures "d1660" horizontal distance of origin L0.start
  measures "d1661" vertical distance of origin L0.start
  measures "d1662" distance of L0.start L0.end
  measures "d1663" distance of L0.end L1.end
extrude "SW2 upper stop 1" add sketch "SW2 upper stop 1 profile" along normal blind 0.8 bodies 2
sketch "SW2 upper stop 2 profile" plane through (0, -1.6638, 19.017) normal (0, -0.087156, 0.996195) x (1, 0, 0)
  line L0 (42.5, 30.4972) -> (43.5, 30.4972)
  line L1 (43.5, 30.4972) -> (43.5, 35.2972)
  line L2 (43.5, 35.2972) -> (42.5, 35.2972)
  line L3 (42.5, 35.2972) -> (42.5, 30.4972)
  dimension "d1666" = 42.5
  dimension "d1667" = 30.4972
  dimension "d1668" = 1
  dimension "d1669" = 4.8
  constraint horizontal L0
  constraint vertical L1
  constraint horizontal L2
  constraint vertical L3
  measures "d1666" horizontal distance of origin L0.start
  measures "d1667" vertical distance of origin L0.start
  measures "d1668" distance of L0.start L0.end
  measures "d1669" distance of L0.end L1.end
extrude "SW2 upper stop 2" add sketch "SW2 upper stop 2 profile" along normal blind 0.8 bodies 2
sketch "SW3 upper stop 1 profile" plane through (0, -1.6638, 19.017) normal (0, -0.087156, 0.996195) x (1, 0, 0)
  line L0 (61, 30.4972) -> (62, 30.4972)
  line L1 (62, 30.4972) -> (62, 35.2972)
  line L2 (62, 35.2972) -> (61, 35.2972)
  line L3 (61, 35.2972) -> (61, 30.4972)
  dimension "d1672" = 61
  dimension "d1673" = 30.4972
  dimension "d1674" = 1
  dimension "d1675" = 4.8
  constraint horizontal L0
  constraint vertical L1
  constraint horizontal L2
  constraint vertical L3
  measures "d1672" horizontal distance of origin L0.start
  measures "d1673" vertical distance of origin L0.start
  measures "d1674" distance of L0.start L0.end
  measures "d1675" distance of L0.end L1.end
extrude "SW3 upper stop 1" add sketch "SW3 upper stop 1 profile" along normal blind 0.8 bodies 2
sketch "SW3 upper stop 2 profile" plane through (0, -1.6638, 19.017) normal (0, -0.087156, 0.996195) x (1, 0, 0)
  line L0 (67, 30.4972) -> (68, 30.4972)
  line L1 (68, 30.4972) -> (68, 35.2972)
  line L2 (68, 35.2972) -> (67, 35.2972)
  line L3 (67, 35.2972) -> (67, 30.4972)
  dimension "d1678" = 67
  dimension "d1679" = 30.4972
  dimension "d1680" = 1
  dimension "d1681" = 4.8
  constraint horizontal L0
  constraint vertical L1
  constraint horizontal L2
  constraint vertical L3
  measures "d1678" horizontal distance of origin L0.start
  measures "d1679" vertical distance of origin L0.start
  measures "d1680" distance of L0.start L0.end
  measures "d1681" distance of L0.end L1.end
extrude "SW3 upper stop 2" add sketch "SW3 upper stop 2 profile" along normal blind 0.8 bodies 2
sketch "SW4 upper stop 1 profile" plane through (0, -1.6638, 19.017) normal (0, -0.087156, 0.996195) x (1, 0, 0)
  line L0 (12, 54.9972) -> (13, 54.9972)
  line L1 (13, 54.9972) -> (13, 59.7972)
  line L2 (13, 59.7972) -> (12, 59.7972)
  line L3 (12, 59.7972) -> (12, 54.9972)
  dimension "d1684" = 12
  dimension "d1685" = 54.9972
  dimension "d1686" = 1
  dimension "d1687" = 4.8
  constraint horizontal L0
  constraint vertical L1
  constraint horizontal L2
  constraint vertical L3
  measures "d1684" horizontal distance of origin L0.start
  measures "d1685" vertical distance of origin L0.start
  measures "d1686" distance of L0.start L0.end
  measures "d1687" distance of L0.end L1.end
extrude "SW4 upper stop 1" add sketch "SW4 upper stop 1 profile" along normal blind 0.8 bodies 2
sketch "SW4 upper stop 2 profile" plane through (0, -1.6638, 19.017) normal (0, -0.087156, 0.996195) x (1, 0, 0)
  line L0 (18, 54.9972) -> (19, 54.9972)
  line L1 (19, 54.9972) -> (19, 59.7972)
  line L2 (19, 59.7972) -> (18, 59.7972)
  line L3 (18, 59.7972) -> (18, 54.9972)
  dimension "d1690" = 18
  dimension "d1691" = 54.9972
  dimension "d1692" = 1
  dimension "d1693" = 4.8
  constraint horizontal L0
  constraint vertical L1
  constraint horizontal L2
  constraint vertical L3
  measures "d1690" horizontal distance of origin L0.start
  measures "d1691" vertical distance of origin L0.start
  measures "d1692" distance of L0.start L0.end
  measures "d1693" distance of L0.end L1.end
extrude "SW4 upper stop 2" add sketch "SW4 upper stop 2 profile" along normal blind 0.8 bodies 2
sketch "SW5 upper stop 1 profile" plane through (0, -1.6638, 19.017) normal (0, -0.087156, 0.996195) x (1, 0, 0)
  line L0 (36.5, 54.9972) -> (37.5, 54.9972)
  line L1 (37.5, 54.9972) -> (37.5, 59.7972)
  line L2 (37.5, 59.7972) -> (36.5, 59.7972)
  line L3 (36.5, 59.7972) -> (36.5, 54.9972)
  dimension "d1696" = 36.5
  dimension "d1697" = 54.9972
  dimension "d1698" = 1
  dimension "d1699" = 4.8
  constraint horizontal L0
  constraint vertical L1
  constraint horizontal L2
  constraint vertical L3
  measures "d1696" horizontal distance of origin L0.start
  measures "d1697" vertical distance of origin L0.start
  measures "d1698" distance of L0.start L0.end
  measures "d1699" distance of L0.end L1.end
extrude "SW5 upper stop 1" add sketch "SW5 upper stop 1 profile" along normal blind 0.8 bodies 2
sketch "SW5 upper stop 2 profile" plane through (0, -1.6638, 19.017) normal (0, -0.087156, 0.996195) x (1, 0, 0)
  line L0 (42.5, 54.9972) -> (43.5, 54.9972)
  line L1 (43.5, 54.9972) -> (43.5, 59.7972)
  line L2 (43.5, 59.7972) -> (42.5, 59.7972)
  line L3 (42.5, 59.7972) -> (42.5, 54.9972)
  dimension "d1702" = 42.5
  dimension "d1703" = 54.9972
  dimension "d1704" = 1
  dimension "d1705" = 4.8
  constraint horizontal L0
  constraint vertical L1
  constraint horizontal L2
  constraint vertical L3
  measures "d1702" horizontal distance of origin L0.start
  measures "d1703" vertical distance of origin L0.start
  measures "d1704" distance of L0.start L0.end
  measures "d1705" distance of L0.end L1.end
extrude "SW5 upper stop 2" add sketch "SW5 upper stop 2 profile" along normal blind 0.8 bodies 2
sketch "SW6 upper stop 1 profile" plane through (0, -1.6638, 19.017) normal (0, -0.087156, 0.996195) x (1, 0, 0)
  line L0 (61, 54.9972) -> (62, 54.9972)
  line L1 (62, 54.9972) -> (62, 59.7972)
  line L2 (62, 59.7972) -> (61, 59.7972)
  line L3 (61, 59.7972) -> (61, 54.9972)
  dimension "d1708" = 61
  dimension "d1709" = 54.9972
  dimension "d1710" = 1
  dimension "d1711" = 4.8
  constraint horizontal L0
  constraint vertical L1
  constraint horizontal L2
  constraint vertical L3
  measures "d1708" horizontal distance of origin L0.start
  measures "d1709" vertical distance of origin L0.start
  measures "d1710" distance of L0.start L0.end
  measures "d1711" distance of L0.end L1.end
extrude "SW6 upper stop 1" add sketch "SW6 upper stop 1 profile" along normal blind 0.8 bodies 2